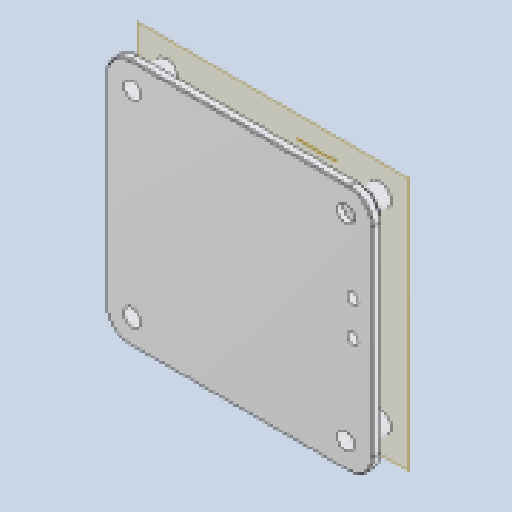
# Autodesk Inventor part: WAS-Enclosure-Top
Saved by Autodesk Inventor 2026.1 (Build 301233020, 233B)
## iProperties
Created: 2025-09-30
Part Number: WAS-Enclosure-Top
Material: ABS Plastic
Document SubType Name: Modeling
Designer: K. Paulsen
Density: 1.06 g/cm^3
Appearance: Smooth - White
Author: K. Paulsen
Autodesk Inventor part; units mm, degrees
ref_plane "YZ Plane" through (0, 0, 0) normal (1, 0, 0) x (0, 1, 0)
ref_plane "XZ Plane" through (0, 0, 0) normal (0, 1, 0) x (-1, 0, 0)
ref_plane "XY Plane" through (0, 0, 0) normal (0, 0, 1) x (1, 0, 0)
sketch "Sketch1" plane through (0, 0, 0) normal (0, 0, 1) x (1, 0, 0)
  line L0 (19.5, 22) -> (-19.5, 22) projected
  arc A0 (23.7, 17.8) -> (19.5, 22) centre (19.5, 17.8) ccw projected
  line L1 (23.7, -17.8) -> (23.7, 17.8) projected
  arc A1 (19.5, -22) -> (23.7, -17.8) centre (19.5, -17.8) ccw projected
  line L2 (-19.5, -22) -> (19.5, -22) projected
  arc A2 (-23.7, -17.8) -> (-19.5, -22) centre (-19.5, -17.8) ccw projected
  line L3 (-23.7, 17.8) -> (-23.7, -17.8) projected
  arc A3 (-19.5, 22) -> (-23.7, 17.8) centre (-19.5, 17.8) ccw projected
  arc A4 (-22.5, -17.8) -> (-19.5, -20.8) centre (-19.5, -17.8) ccw
  line L4 (-19.5, -20.8) -> (19.5, -20.8)
  arc A5 (19.5, -20.8) -> (22.5, -17.8) centre (19.5, -17.8) ccw
  line L5 (22.5, -17.8) -> (22.5, 17.8)
  arc A6 (22.5, 17.8) -> (19.5, 20.8) centre (19.5, 17.8) ccw
  line L6 (19.5, 20.8) -> (-19.5, 20.8)
  arc A7 (-19.5, 20.8) -> (-22.5, 17.8) centre (-19.5, 17.8) ccw
  line L7 (-22.5, 17.8) -> (-22.5, -17.8)
  arc A8 (-20.5, -17.8) -> (-19.5, -18.8) centre (-19.5, -17.8) ccw
  line L8 (-19.5, -18.8) -> (19.5, -18.8)
  arc A9 (19.5, -18.8) -> (20.5, -17.8) centre (19.5, -17.8) ccw
  line L9 (20.5, -17.8) -> (20.5, 17.8)
  arc A10 (20.5, 17.8) -> (19.5, 18.8) centre (19.5, 17.8) ccw
  line L10 (19.5, 18.8) -> (-19.5, 18.8)
  arc A11 (-19.5, 18.8) -> (-20.5, 17.8) centre (-19.5, 17.8) ccw
  line L11 (-20.5, 17.8) -> (-20.5, -17.8)
  point P0 (0, 0)
  dimension "d0" = 1.2
  dimension "d1" = 2
  constraints: 16 end point, 16 point on circle, 8 centre point, 14 other
  measures "d0" distance between parallel lines of L3 L7
  measures "d1" distance between parallel lines of L7 L11
extrude "Extrusion1" add sketch "Sketch1" against normal blind 1 contours L7 A7 L6 A6 L5 A5 L4 A4
draft "FaceDraft1" angle 5 pull direction (0, 0, -1) faces at (-22.5, 5.9333, -0.3333) (-22.4916, 18.0242, -0.6667) (-21.5405, -19.9992, -0.6667) (6.5, 20.8, -0.3333) (-6.5, -20.8, -0.3333) (21.9787, 19.49, -0.6667) (21.19, -20.2787, -0.6667) (22.5, -5.9333, -0.3333) fixed edges at (-22.5, 0, 0) (-21.6213, 19.9213, 0) (-21.6213, -19.9213, 0) (0, 20.8, 0) (0, -20.8, 0) (21.6213, 19.9213, 0) (21.6213, -19.9213, 0) (22.5, 0, 0)
ref_plane "Work Plane1" through (7.78, 21.925, -2.9708) normal (0, 1, 0) x (-1, 0, 0)
sketch "Sketch3" plane through (7.78, 21.925, -2.9708) normal (0, 1, 0) x (-1, 0, 0)
  arc A0 (1.25, 0.66) -> (0, 1.91) centre (0, 0.66) ccw construction
  arc A1 (-6.44, 1.91) -> (-7.69, 0.66) centre (-6.44, 0.66) ccw construction
  line L0 (-6.44, 1.91) -> (0, 1.91) construction
  arc A2 (-6.44, 2.31) -> (-8.09, 0.66) centre (-6.44, 0.66) ccw
  line L1 (-6.44, 2.31) -> (0, 2.31)
  arc A3 (1.65, 0.66) -> (0, 2.31) centre (0, 0.66) ccw
  line L2 (-8.09, 0.065) -> (-8.09, 2.7708) projected
  line L3 (-8.09, 0.66) -> (1.65, 0.66)
  point P0 (7.78, 2.9708)
  constraints: 4 end point, 4 point on circle, 2 centre point, 1 perpendicular, 1 tangent, 2 other
extrude "Extrusion2" cut sketch "Sketch3" against normal up to surface (3.125 mm away)
sketch "Sketch4" plane through (0, 0, 0) normal (0, 0, 1) x (1, 0, 0)
  line L0 (19.5, 22) -> (-19.5, 22) projected
  arc A0 (23.7, 17.8) -> (19.5, 22) centre (19.5, 17.8) ccw projected
  line L1 (23.7, -17.8) -> (23.7, 17.8) projected
  arc A1 (19.5, -22) -> (23.7, -17.8) centre (19.5, -17.8) ccw projected
  line L2 (-19.5, -22) -> (19.5, -22) projected
  arc A2 (-23.7, -17.8) -> (-19.5, -22) centre (-19.5, -17.8) ccw projected
  line L3 (-23.7, 17.8) -> (-23.7, -17.8) projected
  arc A3 (-19.5, 22) -> (-23.7, 17.8) centre (-19.5, 17.8) ccw projected
  point P0 (0, 0)
extrude "Extrusion3" add sketch "Sketch4" along normal blind 1.6
sketch "Sketch5" plane through (0, 0, 1.6) normal (0, 0, 1) x (1, 0, 0)
  circle A0 centre (-19, 17.5) radius 1.1 construction
  circle A1 centre (-19, -17.5) radius 1.1 construction
  circle A2 centre (19, -17.5) radius 1.1 construction
  circle A3 centre (19, 17.5) radius 1.1 construction
  point P0 (0, 0)
hole "Hole1" at (-19, 17.5, 1.6) at (19, 17.5, 1.6) at (19, -17.5, 1.6) at (-19, -17.5, 1.6) direction (0, 0, -1) diameter 3 end through all
ref_plane "Work Plane2" through (-108, 117.5, -4.3998) normal (0, 0, 1) x (1, 0, 0)
sketch "Sketch7" plane through (-108, 117.5, -4.3998) normal (0, 0, 1) x (1, 0, 0)
  arc A0 (89.7483, -136.3) -> (87.5, -135) centre (89, -135) ccw construction
  arc A1 (127.8474, -136.2377) -> (128.5, -135) centre (127, -135) ccw construction
  arc A2 (126.2517, -98.7) -> (128.5, -100) centre (127, -100) ccw projected
  arc A3 (88.1526, -98.7623) -> (87.5, -100) centre (89, -100) ccw construction
  circle A4 centre (89, -135) radius 2
  circle A5 centre (127, -135) radius 2
  circle A6 centre (127, -100) radius 2
  circle A7 centre (89, -100) radius 1.5 projected
  circle A8 centre (89, -100) radius 2
  circle A9 centre (127, -100) radius 1.5
  circle A10 centre (127, -135) radius 1.5
  circle A11 centre (89, -135) radius 1.5
  point P0 (108, -117.5)
  point P1 (126.2517, -136.3)
  point P2 (89.7483, -98.7)
  dimension "d21" = 4
  constraints: 7 coincident, 6 centre point, 3 equal radius, 2 point on circle, 3 other
  measures "d21" diameter of A4
extrude "Extrusion5" add sketch "Sketch7" along normal blind 5
sketch "Sketch8" plane through (0, 0, 1.6) normal (0, 0, 1) x (1, 0, 0)
  circle A0 centre (20.25, -1.1) radius 0.85 construction
  circle A1 centre (20.25, 5) radius 0.85 construction
  circle A2 centre (20.25, 5) radius 1
  circle A3 centre (20.25, -1.1) radius 1
  point P0 (0, 0)
  dimension "d25" = 2
  dimension "d26" = 2
  constraints: 2 centre point, 2 coincident
  measures "d25" diameter of A2
  measures "d26" diameter of A3
extrude "Extrusion6" cut sketch "Sketch8" against normal through all
fillet "Fillet4" radius 1 4 edges at (20.5, 5.9682, -0.5) (20.5, 4.0318, -0.5) (20.5, -0.1318, -0.5) (20.5, -2.0682, -0.5)
chamfer "Chamfer1" distance 0.2 angle 45 16 edges at (23.7, 0, 1.6) (22.4698, 20.7698, 1.6) (0, 22, 1.6) (-22.4698, 20.7698, 1.6) (-23.7, 0, 1.6) (-22.4698, -20.7698, 1.6) (0, -22, 1.6) (22.4698, -20.7698, 1.6) (-23.7, 0, 0) (-22.4698, -20.7698, 0) (0, -22, 0) (22.4698, -20.7698, 0) (23.7, 0, 0) (22.4698, 20.7698, 0) (0, 22, 0) (-22.4698, 20.7698, 0)
sketch "Sketch10" plane through (0, 0, -1) normal (0, 0, -1) x (-1, 0, 0)
  line L0 (6.985, -16.187) -> (6.985, -17.813) construction
  line L1 (-0.015, -17.813) -> (-0.015, -16.187) construction
  line L2 (-0.015, -17.813) -> (-0.015, -20.8) construction
  line L3 (17.4801, -18.8) -> (-17.4801, -18.8) projected
  line L4 (-19.5, -20.8) -> (19.5, -20.8) projected
  line L5 (6.985, -17.813) -> (6.985, -20.8) construction
  line L6 (6.985, -17.813) -> (9.972, -17.813) construction
  line L7 (7.185, -20.8) -> (7.185, -18.013)
  line L8 (7.185, -18.013) -> (9.972, -18.013)
  line L9 (-0.215, -20.8) -> (-0.215, -17.813)
  line L10 (-0.215, -17.813) -> (-0.215, -16.187)
  point P0 (0, 0)
  point P1 (15.6955, -18.7)
  point P2 (-15.6955, -18.7)
  point P3 (-0.215, -18.8)
  point P4 (7.185, -18.8)
  dimension "d33" = 90
  dimension "d34" = 0.2
  dimension "d35" = 0.2
  constraints: 14 end point, 3 point on line, 2 perpendicular, 1 horizontal, 1 vertical, 3 other
  measures "d33" angle of L5 L6
  measures "d34" distance between parallel lines of L5 L7
  measures "d35" distance between parallel lines of L2 L9
extrude "Extrusion7" cut sketch "Sketch10" against normal up to surface (1 mm away)
fillet "Fillet5" radius 0.6 4 edges at (0.215, -18.8, -0.5) (0.215, -20.7563, -0.5) (-7.185, -18.8, -0.5) (-7.185, -20.7563, -0.5)
fillet "Fillet6" radius 2 8 edges at (17.4801, -18.8, -0.5) (20.5, -16.1771, -0.5) (17.4801, 18.8, -0.5) (20.5, 16.1771, -0.5) (-17.4801, 18.8, -0.5) (-20.5, 16.1771, -0.5) (-20.5, -16.1771, -0.5) (-17.4801, -18.8, -0.5)
body "Solid1"
